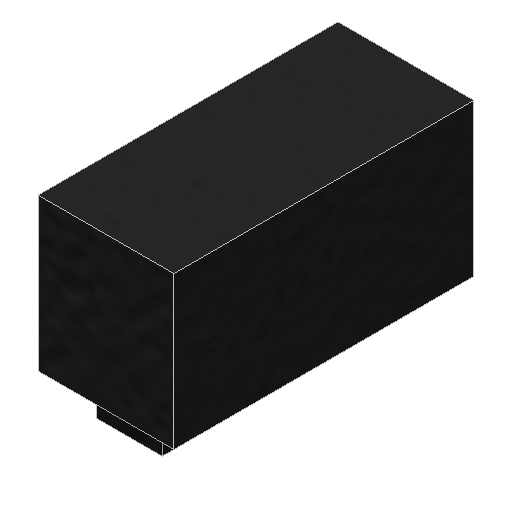
# Autodesk Inventor part: BUY - Omron - micro switch - D2F-L - OT2-Pipette V0.3 placeholder
Saved by Autodesk Inventor 2025.5 (Build 295498000, 498)
## iProperties
Created: 2026-11-01
Part Number: BUY - Omron - micro switch - D2F-L - OT2-Pipette V0.3 placeholder
Material: Generisch
Description: home switch placeholder (Omron D2F-L class body + lever)
Document SubType Name: Modeling
Designer: benir
Density: 1 g/cm^3
Appearance: Black
Author: benir
Autodesk Inventor part; units mm, degrees
ref_plane "XZ Plane" through (0, 0, 0) normal (0, 1, 0) x (-1, 0, 0)
ref_plane "x=wall_x1" through (-2.2, 0, 0) normal (1, 0, 0) x (0, 1, 0)
sketch "switch body" plane through (-2.2, 0, 0) normal (1, 0, 0) x (0, 1, 0)
  line L0 (103.7, -16) -> (110.2, -16)
  line L1 (110.2, -16) -> (110.2, -3.2)
  line L2 (110.2, -3.2) -> (103.7, -3.2)
  line L3 (103.7, -3.2) -> (103.7, -16)
  line L4 (0, -19.2) -> (0, 3.2) projected
  line L5 (-22.04, 0) -> (132.24, 0) projected
  point P0 (0, 0)
  dimension "d3" = 6.5
  dimension "d4" = 12.8
  dimension "d5" = 103.7
  dimension "d6" = 16
  constraints: 8 end point, 2 parallel, 1 horizontal, 1 perpendicular
  measures "d3" distance of L0.start L0.end
  measures "d4" distance of L2.end L0.start
  measures "d5" horizontal distance of point (0, 0) L2.end
  measures "d6" vertical distance of point (0, 0) L0.start
extrude "Extrusion2" add sketch "switch body" along normal blind 5.8
ref_plane "x=wall_x1 + lever_x0" through (-0.7, 0, 0) normal (1, 0, 0) x (0, 1, 0)
sketch "lever" plane through (-0.7, 0, 0) normal (1, 0, 0) x (0, 1, 0)
  line L0 (102.2, -15) -> (103.7, -15)
  line L1 (103.7, -15) -> (103.7, -4.2)
  line L2 (103.7, -4.2) -> (102.2, -4.2)
  line L3 (102.2, -4.2) -> (102.2, -15)
  line L4 (0, -19.2) -> (0, 3.2) projected
  line L5 (-22.04, 0) -> (132.24, 0) projected
  point P0 (0, 0)
  dimension "d10" = 1.5
  dimension "d11" = 10.8
  dimension "d12" = 102.2
  dimension "d13" = 15
  constraints: 8 end point, 2 parallel, 1 horizontal, 1 perpendicular
  measures "d10" distance of L0.start L0.end
  measures "d11" distance of L2.end L0.start
  measures "d12" horizontal distance of point (0, 0) L2.end
  measures "d13" vertical distance of point (0, 0) L0.start
extrude "Extrusion3" add sketch "lever" along normal blind 2.8
equation "\"d3\" = sw_h + 0 * sw_y0"
equation "\"d4\" = sw_l + 0 * sw_z0"
equation "\"d5\" = sw_y0"
equation "\"d6\" = -sw_z0"
equation "\"d7\" = sw_w"
equation "\"d10\" = 0 * sw_y0 + lever_drop"
equation "\"d11\" = -2 * lever_inset + 0 * sw_z0 + sw_l"
equation "\"d12\" = sw_y0 - lever_drop"
equation "\"d13\" = -lever_inset - sw_z0"
equation "\"d14\" = lever_x1 - lever_x0"
equation "\"sw_h\" = 6.5"
equation "\"sw_y0\" = 103.7"
equation "\"sw_l\" = 12.8"
equation "\"sw_z0\" = -16"
equation "\"sw_w\" = 5.8"
equation "\"lever_drop\" = 1.5"
equation "\"lever_inset\" = 1"
equation "\"lever_x1\" = 4.3"
equation "\"lever_x0\" = 1.5"
body "Solid2"
